Orange_BottomCover_v2 (Autodesk Fusion 360 design; units mm, degrees)
part number: 2026-11-06-04-55-55-977
Autodesk Fusion 360 part; units mm, degrees
ref_plane "WorkPlane1" through (0, 0, -7.6) normal (0, 0, 1) x (1, 0, 0)
sketch "Plate" plane through (0, 0, -7.6) normal (0, 0, 1) x (1, 0, 0)
  line L0 (-35, -28.06) -> (88.6, -28.06)
  line L1 (88.6, -28.06) -> (88.6, 23.3)
  line L2 (88.6, 23.3) -> (-35, 23.3)
  line L3 (-35, 23.3) -> (-35, -28.06)
extrude "Plate (1)" add sketch "Plate" along normal blind 3.6 makes body 1
ref_plane "WorkPlane2" through (0, 0, -4) normal (0, 0, 1) x (1, 0, 0)
sketch "WallL" plane through (0, 0, -4) normal (0, 0, 1) x (1, 0, 0)
  line L0 (-35, -28.06) -> (82.6, -28.06)
  line L1 (82.6, -28.06) -> (82.6, -26.46)
  line L2 (82.6, -26.46) -> (-35, -26.46)
  line L3 (-35, -26.46) -> (-35, -28.06)
extrude "WallL (1)" add sketch "WallL" along normal blind 3 bodies 1
ref_plane "WorkPlane3" through (0, 0, -4) normal (0, 0, 1) x (1, 0, 0)
sketch "WallR" plane through (0, 0, -4) normal (0, 0, 1) x (1, 0, 0)
  line L0 (-35, 21.7) -> (82.6, 21.7)
  line L1 (82.6, 21.7) -> (82.6, 23.3)
  line L2 (82.6, 23.3) -> (-35, 23.3)
  line L3 (-35, 23.3) -> (-35, 21.7)
extrude "WallR (1)" add sketch "WallR" along normal blind 3 bodies 1
ref_plane "WorkPlane4" through (0, 0, -7.6) normal (0, 0, 1) x (1, 0, 0)
sketch "TabRoot" plane through (0, 0, -7.6) normal (0, 0, 1) x (1, 0, 0)
  line L0 (-37.2, -9.18) -> (-35, -9.18)
  line L1 (-35, -9.18) -> (-35, 4.42)
  line L2 (-35, 4.42) -> (-37.2, 4.42)
  line L3 (-37.2, 4.42) -> (-37.2, -9.18)
extrude "TabRoot (1)" add sketch "TabRoot" along normal blind 3.6 bodies 1
ref_plane "WorkPlane5" through (0, 0, -4) normal (0, 0, 1) x (1, 0, 0)
sketch "RearTab" plane through (0, 0, -4) normal (0, 0, 1) x (1, 0, 0)
  line L0 (-37.2, -9.18) -> (-35.2, -9.18)
  line L1 (-35.2, -9.18) -> (-35.2, 4.42)
  line L2 (-35.2, 4.42) -> (-37.2, 4.42)
  line L3 (-37.2, 4.42) -> (-37.2, -9.18)
extrude "RearTab (1)" add sketch "RearTab" along normal blind 3.4 bodies 1
ref_plane "WorkPlane6" through (0, -9.18, 0) normal (0, 1, 0) x (0, 0, 1)
sketch "Tongue" plane through (0, -9.18, 0) normal (0, 1, 0) x (1, 0, 0)
  line L0 (-35.2, 2.5) -> (-33.8, 2.5)
  line L1 (-33.8, 2.5) -> (-33.8, 1.6)
  line L2 (-33.8, 1.6) -> (-35.2, 1.2)
  line L3 (-35.2, 1.2) -> (-35.2, 2.5)
extrude "Tongue (1)" add sketch "Tongue" along normal blind 13.6 bodies 1
ref_plane "WorkPlane7" through (0, 0, -7.6) normal (0, 0, 1) x (1, 0, 0)
sketch "ArmRoot" plane through (0, 0, -7.6) normal (0, 0, 1) x (1, 0, 0)
  line L0 (88.6, -8.18) -> (90, -8.18)
  line L1 (90, -8.18) -> (90, 3.42)
  line L2 (90, 3.42) -> (88.6, 3.42)
  line L3 (88.6, 3.42) -> (88.6, -8.18)
extrude "ArmRoot (1)" add sketch "ArmRoot" along normal blind 3 bodies 1
ref_plane "WorkPlane8" through (0, 0, -4.6) normal (0, 0, 1) x (1, 0, 0)
sketch "LatchArm" plane through (0, 0, -4.6) normal (0, 0, 1) x (1, 0, 0)
  line L0 (89, -8.18) -> (90, -8.18)
  line L1 (90, -8.18) -> (90, 3.42)
  line L2 (90, 3.42) -> (89, 3.42)
  line L3 (89, 3.42) -> (89, -8.18)
extrude "LatchArm (1)" add sketch "LatchArm" along normal blind 10.6 bodies 1
ref_plane "WorkPlane9" through (0, -8.18, 0) normal (0, 1, 0) x (0, 0, 1)
sketch "Hook" plane through (0, -8.18, 0) normal (0, 1, 0) x (1, 0, 0)
  line L0 (89, -4.4) -> (87.5, -4.4)
  line L1 (87.5, -4.4) -> (87.5, -4.8)
  line L2 (87.5, -4.8) -> (89, -5.6)
  line L3 (89, -5.6) -> (89, -4.4)
extrude "Hook (1)" add sketch "Hook" along normal blind 11.6 bodies 1
ref_plane "WorkPlane10" through (0, 0, 5) normal (0, 0, 1) x (1, 0, 0)
sketch "PullTab" plane through (0, 0, 5) normal (0, 0, 1) x (1, 0, 0)
  line L0 (90, -8.18) -> (93.6, -8.18)
  line L1 (93.6, -8.18) -> (93.6, 3.42)
  line L2 (93.6, 3.42) -> (90, 3.42)
  line L3 (90, 3.42) -> (90, -8.18)
extrude "PullTab (1)" add sketch "PullTab" along normal blind 1 bodies 1
ref_plane "WorkPlane11" through (0, 0, -7.6) normal (0, 0, 1) x (1, 0, 0)
sketch "screw_0" plane through (0, 0, -7.6) normal (0, 0, 1) x (1, 0, 0)
  circle A0 centre (-33, 10) radius 1.2
extrude "ScrewHole0" cut sketch "screw_0" along normal blind 3.7 bodies 1
ref_plane "WorkPlane12" through (0, 0, -7.6) normal (0, 0, 1) x (1, 0, 0)
sketch "screw_1" plane through (0, 0, -7.6) normal (0, 0, 1) x (1, 0, 0)
  circle A0 centre (-33, -14) radius 1.2
extrude "ScrewHole1" cut sketch "screw_1" along normal blind 3.7 bodies 1
ref_plane "WorkPlane13" through (0, 0, -7.6) normal (0, 0, 1) x (1, 0, 0)
sketch "screw_2" plane through (0, 0, -7.6) normal (0, 0, 1) x (1, 0, 0)
  circle A0 centre (85, 10) radius 1.2
extrude "ScrewHole2" cut sketch "screw_2" along normal blind 3.7 bodies 1
ref_plane "WorkPlane14" through (0, 0, -7.6) normal (0, 0, 1) x (1, 0, 0)
sketch "screw_3" plane through (0, 0, -7.6) normal (0, 0, 1) x (1, 0, 0)
  circle A0 centre (85, -14) radius 1.2
extrude "ScrewHole3" cut sketch "screw_3" along normal blind 3.7 bodies 1
chamfer "Countersinks" distance 1 angle 45 4 edges at (83.8812, -14.4339, -7.6) (83.8812, 9.5661, -7.6) (-34.1188, -14.4339, -7.6) (-34.1188, 9.5661, -7.6) tangent chain off on bodies 1
chamfer "RockBevel" distance 0.8 angle 45 2 edges at (-35, 13.06, -4) (-35, -17.82, -4) tangent chain off on bodies 1
chamfer "OuterChamfer" distance 1 angle 45 4 edges at (-30.8, 10, -7.6) (26.8, 23.3, -7.6) (26.8, -28.06, -7.6) (-30.8, -14, -7.6) tangent chain off on bodies 1
ref_plane "WorkPlane15" through (0, 0, -7.6) normal (0, 0, 1) x (1, 0, 0)
sketch "pocket_Spine1" plane through (0, 0, -7.6) normal (0, 0, 1) x (1, 0, 0)
  line L0 (-16, -12.38) -> (0.8, -12.38)
  line L1 (0.8, -12.38) -> (0.8, 7.62)
  line L2 (0.8, 7.62) -> (-16, 7.62)
  line L3 (-16, 7.62) -> (-22, 1.62)
  line L4 (-22, 1.62) -> (-22, -6.38)
  line L5 (-22, -6.38) -> (-16, -12.38)
extrude "PocketSpine1" cut sketch "pocket_Spine1" along normal blind 2 bodies 1
ref_plane "WorkPlane16" through (0, 0, -7.6) normal (0, 0, 1) x (1, 0, 0)
sketch "InlaySpine1" plane through (0, 0, -7.6) normal (0, 0, 1) x (1, 0, 0)
  line L0 (-15.9379, -12.23) -> (0.65, -12.23)
  line L1 (0.65, -12.23) -> (0.65, 7.47)
  line L2 (0.65, 7.47) -> (-15.9379, 7.47)
  line L3 (-15.9379, 7.47) -> (-21.85, 1.5579)
  line L4 (-21.85, 1.5579) -> (-21.85, -6.3179)
  line L5 (-21.85, -6.3179) -> (-15.9379, -12.23)
extrude "InlaySpine1 (1)" add sketch "InlaySpine1" along normal blind 2 separate body makes body 2
ref_plane "WorkPlane17" through (0, 0, -7.6) normal (0, 0, 1) x (1, 0, 0)
sketch "pocket_Spine2" plane through (0, 0, -7.6) normal (0, 0, 1) x (1, 0, 0)
  line L0 (2.4, -12.38) -> (25.2, -12.38)
  line L1 (25.2, -12.38) -> (25.2, 7.62)
  line L2 (25.2, 7.62) -> (2.4, 7.62)
  line L3 (2.4, 7.62) -> (2.4, -12.38)
extrude "PocketSpine2" cut sketch "pocket_Spine2" along normal blind 2 bodies 1
ref_plane "WorkPlane18" through (0, 0, -7.6) normal (0, 0, 1) x (1, 0, 0)
sketch "InlaySpine2" plane through (0, 0, -7.6) normal (0, 0, 1) x (1, 0, 0)
  line L0 (2.55, -12.23) -> (25.05, -12.23)
  line L1 (25.05, -12.23) -> (25.05, 7.47)
  line L2 (25.05, 7.47) -> (2.55, 7.47)
  line L3 (2.55, 7.47) -> (2.55, -12.23)
extrude "InlaySpine2 (1)" add sketch "InlaySpine2" along normal blind 2 separate body makes body 3
ref_plane "WorkPlane19" through (0, 0, -7.6) normal (0, 0, 1) x (1, 0, 0)
sketch "pocket_Spine3" plane through (0, 0, -7.6) normal (0, 0, 1) x (1, 0, 0)
  line L0 (26.8, -12.38) -> (49.6, -12.38)
  line L1 (49.6, -12.38) -> (49.6, 7.62)
  line L2 (49.6, 7.62) -> (26.8, 7.62)
  line L3 (26.8, 7.62) -> (26.8, -12.38)
extrude "PocketSpine3" cut sketch "pocket_Spine3" along normal blind 2 bodies 1
ref_plane "WorkPlane20" through (0, 0, -7.6) normal (0, 0, 1) x (1, 0, 0)
sketch "InlaySpine3" plane through (0, 0, -7.6) normal (0, 0, 1) x (1, 0, 0)
  line L0 (26.95, -12.23) -> (49.45, -12.23)
  line L1 (49.45, -12.23) -> (49.45, 7.47)
  line L2 (49.45, 7.47) -> (26.95, 7.47)
  line L3 (26.95, 7.47) -> (26.95, -12.23)
extrude "InlaySpine3 (1)" add sketch "InlaySpine3" along normal blind 2 separate body makes body 4
ref_plane "WorkPlane21" through (0, 0, -7.6) normal (0, 0, 1) x (1, 0, 0)
sketch "pocket_Spine4" plane through (0, 0, -7.6) normal (0, 0, 1) x (1, 0, 0)
  line L0 (51.2, -12.38) -> (68, -12.38)
  line L1 (68, -12.38) -> (74, -6.38)
  line L2 (74, -6.38) -> (74, 1.62)
  line L3 (74, 1.62) -> (68, 7.62)
  line L4 (68, 7.62) -> (51.2, 7.62)
  line L5 (51.2, 7.62) -> (51.2, -12.38)
extrude "PocketSpine4" cut sketch "pocket_Spine4" along normal blind 2 bodies 1
ref_plane "WorkPlane22" through (0, 0, -7.6) normal (0, 0, 1) x (1, 0, 0)
sketch "InlaySpine4" plane through (0, 0, -7.6) normal (0, 0, 1) x (1, 0, 0)
  line L0 (51.35, -12.23) -> (67.9379, -12.23)
  line L1 (67.9379, -12.23) -> (73.85, -6.3179)
  line L2 (73.85, -6.3179) -> (73.85, 1.5579)
  line L3 (73.85, 1.5579) -> (67.9379, 7.47)
  line L4 (67.9379, 7.47) -> (51.35, 7.47)
  line L5 (51.35, 7.47) -> (51.35, -12.23)
extrude "InlaySpine4 (1)" add sketch "InlaySpine4" along normal blind 2 separate body makes body 5
ref_plane "WorkPlane23" through (0, 0, -7.6) normal (0, 0, 1) x (1, 0, 0)
sketch "pocket_StripeR" plane through (0, 0, -7.6) normal (0, 0, 1) x (1, 0, 0)
  line L0 (-18, 12) -> (70, 12)
  line L1 (70, 12) -> (72.6, 14.6)
  line L2 (72.6, 14.6) -> (-15.4, 14.6)
  line L3 (-15.4, 14.6) -> (-18, 12)
extrude "PocketStripeR" cut sketch "pocket_StripeR" along normal blind 2 bodies 1
ref_plane "WorkPlane24" through (0, 0, -7.6) normal (0, 0, 1) x (1, 0, 0)
sketch "InlayStripeR" plane through (0, 0, -7.6) normal (0, 0, 1) x (1, 0, 0)
  line L0 (-17.6379, 12.15) -> (69.9379, 12.15)
  line L1 (69.9379, 12.15) -> (72.2379, 14.45)
  line L2 (72.2379, 14.45) -> (-15.3379, 14.45)
  line L3 (-15.3379, 14.45) -> (-17.6379, 12.15)
extrude "InlayStripeR (1)" add sketch "InlayStripeR" along normal blind 2 separate body makes body 6
ref_plane "WorkPlane25" through (0, 0, -7.6) normal (0, 0, 1) x (1, 0, 0)
sketch "pocket_StripeL" plane through (0, 0, -7.6) normal (0, 0, 1) x (1, 0, 0)
  line L0 (-15.4, -19.36) -> (72.6, -19.36)
  line L1 (72.6, -19.36) -> (70, -16.76)
  line L2 (70, -16.76) -> (-18, -16.76)
  line L3 (-18, -16.76) -> (-15.4, -19.36)
extrude "PocketStripeL" cut sketch "pocket_StripeL" along normal blind 2 bodies 1
ref_plane "WorkPlane26" through (0, 0, -7.6) normal (0, 0, 1) x (1, 0, 0)
sketch "InlayStripeL" plane through (0, 0, -7.6) normal (0, 0, 1) x (1, 0, 0)
  line L0 (-15.3379, -19.21) -> (72.2379, -19.21)
  line L1 (72.2379, -19.21) -> (69.9379, -16.91)
  line L2 (69.9379, -16.91) -> (-17.6379, -16.91)
  line L3 (-17.6379, -16.91) -> (-15.3379, -19.21)
extrude "InlayStripeL (1)" add sketch "InlayStripeL" along normal blind 2 separate body makes body 7
named bodies: "BottomCover", "Inlay_Spine1", "Inlay_Spine2", "Inlay_Spine3", "Inlay_Spine4", "Inlay_StripeR", "Inlay_StripeL"
